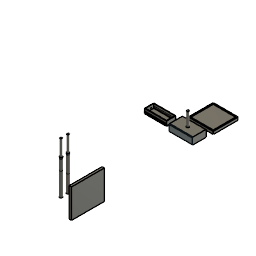
Fuji Personal (Autodesk Fusion 360 design; units mm, degrees)
part number: 2026-10-13-20-22-36-203
Autodesk Fusion 360 part; units mm, degrees
sketch "Sketch1" plane through (0, 0, 0) normal (0, 1, 0) x (1, 0, 0)
  line L0 (-50, 50) -> (50, 50)
  line L1 (50, 50) -> (50, -50)
  line L2 (50, -50) -> (-50, -50)
  line L3 (-50, -50) -> (-50, 50)
  constraint horizontal L0
  constraint vertical L1
  constraint horizontal L2
  constraint vertical L3
sketch "Sketch2" plane through (0, 0, 0) normal (0, 1, 0) x (1, 0, 0)
  line L0 (-95, -40.1567) -> (-192.2, -40.1567)
  line L1 (-192.2, -40.1567) -> (-192.2, 57.0433)
  line L2 (-192.2, 57.0433) -> (-95, 57.0433)
  line L3 (-95, 57.0433) -> (-95, -40.1567)
  dimension "d5" = 97.2
  dimension "d6" = 97.2
  constraint horizontal L0
  constraint vertical L1
  constraint horizontal L2
  constraint vertical L3
  measures "d5" distance of L0.start L2.end
  measures "d6" distance of L0.start L0.end
sketch "Sketch3" plane through (0, 0, 0) normal (0, 1, 0) x (1, 0, 0)
  line L0 (100, -40) -> (-7.2, -40)
  line L1 (-7.2, -40) -> (-7.2, 67.2)
  line L2 (-7.2, 67.2) -> (100, 67.2)
  line L3 (100, 67.2) -> (100, -40)
  dimension "d9" = 107.2
  dimension "d10" = 107.2
  constraint horizontal L0
  constraint vertical L1
  constraint horizontal L2
  constraint vertical L3
  measures "d9" distance of L0.start L0.end
  measures "d10" distance of L0.start L2.end
sketch "Sketch4" plane through (-2.2, 0, 0) normal (-1, 0, 0) x (0, 0, 1)
  line L0 (-62.0433, 10) -> (35.1567, 10)
  line L1 (35.1567, 10) -> (35.1567, 107.2)
  line L2 (35.1567, 107.2) -> (-62.0433, 107.2)
  line L3 (-62.0433, 107.2) -> (-62.0433, 10)
  line L4 (-60, 105) -> (32, 105)
  line L5 (32, 105) -> (32, 13)
  line L6 (32, 13) -> (-60, 13)
  line L7 (-60, 13) -> (-60, 105)
  dimension "d13" = 92
  dimension "d14" = 92
  constraint horizontal L4
  constraint vertical L5
  constraint horizontal L6
  constraint vertical L7
  measures "d13" distance of L4.start L4.end
  measures "d14" distance of L4.start L6.end
sketch "Sketch5" plane through (0, 10, 0) normal (0, 1, 0) x (-1, 0, 0)
  line L0 (-100, -67.2) -> (7.2, -67.2)
  line L1 (7.2, -67.2) -> (7.2, 40)
  line L2 (7.2, 40) -> (-100, 40)
  line L3 (-100, 40) -> (-100, -67.2)
  line L4 (3, -63) -> (6, -63)
  line L5 (6, -63) -> (6, 36)
  line L6 (6, 36) -> (3, 36)
  line L7 (3, 36) -> (3, -63)
  constraint horizontal L4
  constraint vertical L5
  constraint horizontal L6
  constraint vertical L7
sketch "Sketch7" plane through (0, 0, 0) normal (0, -1, 0) x (1, 0, 0)
  line L0 (-7.2, -67.2) -> (100, -67.2)
  line L1 (100, -67.2) -> (100, 40)
  line L2 (100, 40) -> (-7.2, 40)
  line L3 (-7.2, 40) -> (-7.2, -67.2)
  circle A0 centre (46.3894, -13.587) radius 5
  dimension "d20" = 10
  measures "d20" diameter of A0
sketch "Sketch8" plane through (0, 0, 0) normal (0, 1, 0) x (1, 0, 0)
  circle A0 centre (-120, 50) radius 5
  dimension "d23" = 10
  measures "d23" diameter of A0
extrude "Extrude7" add sketch "Sketch8" along normal blind 35 makes body 1
extrude "Extrude8" add 1 faces at (-118.5319, 35, -51.1707) along direction (0, 1, 0) blind 10 on bodies 1 bodies 1
sketch "Sketch9" plane through (0, 0, 0) normal (0, 1, 0) x (1, 0, 0)
  line L0 (-35, -25) -> (-125, -25)
  line L1 (-125, -25) -> (-125, -80)
  line L2 (-125, -80) -> (-35, -80)
  line L3 (-35, -80) -> (-35, -25)
  constraint horizontal L0
  constraint vertical L1
  constraint horizontal L2
  constraint vertical L3
sketch "Sketch10" plane through (0, 4, 0) normal (0, 1, 0) x (-1, 0, 0)
  arc A0 (37.5, 80) -> (35, 77.5) centre (37.5, 77.5) ccw
  line L0 (35, 77.5) -> (35, 27.5)
  arc A1 (35, 27.5) -> (37.5, 25) centre (37.5, 27.5) ccw
  line L1 (37.5, 25) -> (122.5, 25)
  arc A2 (122.5, 25) -> (125, 27.5) centre (122.5, 27.5) ccw
  line L2 (125, 27.5) -> (125, 77.5)
  arc A3 (125, 77.5) -> (122.5, 80) centre (122.5, 77.5) ccw
  line L3 (122.5, 80) -> (37.5, 80)
  line L4 (35, 52.5) -> (125, 52.5)
  line L5 (80, 80) -> (80, 25)
  circle A4 centre (80, 52.5) radius 4.9
  dimension "d34" = 9.8
  constraint midpoint L0 L4.start
  constraint midpoint L2 L4.end
  constraint midpoint L3 L5.start
  constraint midpoint L1 L5.end
  constraint midpoint L5 A4.centre
  measures "d34" diameter of A4
move_body "Move3" bodies 1 to x (1, 0, 0) y (0, 1, 0) z (0, 0, 1) at (40, 0, 102.5)
sketch "Sketch11" plane through (0, 0, 0) normal (0, 1, 0) x (1, 0, 0)
  line L0 (-125, -130) -> (-10, -130)
  line L1 (-10, -130) -> (-10, -150)
  line L2 (-10, -150) -> (-125, -150)
  line L3 (-125, -150) -> (-125, -130)
  line L4 (-125, -150) -> (-10, -150)
  line L5 (-10, -150) -> (-10, -175)
  line L6 (-10, -175) -> (-125, -175)
  line L7 (-125, -175) -> (-125, -150)
  constraint horizontal L0
  constraint vertical L1
  constraint horizontal L2
  constraint vertical L3
  constraint horizontal L4
  constraint vertical L5
  constraint horizontal L6
  constraint vertical L7
sketch "Sketch13" plane through (0, 35, 0) normal (0, 1, 0) x (-1, 0, 0)
  line L0 (125, 175) -> (10, 175)
  line L1 (10, 175) -> (10, 130)
  line L2 (10, 130) -> (125, 130)
  line L3 (125, 130) -> (125, 175)
  line L4 (125, 130) -> (10, 130)
  line L5 (10, 130) -> (10, 175)
  line L6 (10, 175) -> (125, 175)
  line L7 (125, 175) -> (125, 130)
  line L8 (123.5, 131.5) -> (11.5, 131.5)
  line L9 (11.5, 131.5) -> (11.5, 135.5)
  line L10 (11.5, 135.5) -> (123.5, 135.5)
  line L11 (123.5, 135.5) -> (123.5, 131.5)
  line L12 (11.5, 135.5) -> (123, 135.5)
  line L13 (123, 135.5) -> (123, 173.5)
  line L14 (123, 173.5) -> (11.5, 173.5)
  line L15 (11.5, 173.5) -> (11.5, 135.5)
  line L16 (123, 173.5) -> (123.5, 173.5)
  line L17 (123.5, 173.5) -> (123.5, 135.5)
  line L18 (123.5, 135.5) -> (123, 135.5)
  line L19 (123, 135.5) -> (123, 173.5)
  dimension "d41" = 115
  dimension "d42" = 45
  constraint horizontal L4
  constraint vertical L5
  constraint horizontal L6
  constraint vertical L7
  constraint coincident L0.end L1.start
  constraint coincident L2.end L3.start
  constraint horizontal L8
  constraint vertical L9
  constraint horizontal L10
  constraint vertical L11
  constraint horizontal L12
  constraint vertical L13
  constraint horizontal L14
  constraint vertical L15
  constraint horizontal L16
  constraint vertical L17
  constraint horizontal L18
  constraint vertical L19
  measures "d41" distance of L2.end L1.end
  measures "d42" distance of L2.end L0.start
sketch "Sketch14" plane through (0, 54.4449, 0) normal (0, 1, 0) x (-1, 0, 0)
  arc A0 (133.3754, 102.0813) -> (129.3754, 106.0813) centre (129.3754, 102.0813) ccw
  line L0 (129.3754, 106.0813) -> (30.1754, 106.0813)
  arc A1 (30.1754, 106.0813) -> (26.1754, 102.0813) centre (30.1754, 102.0813) ccw
  line L1 (26.1754, 102.0813) -> (26.1754, 2.8813)
  arc A2 (26.1754, 2.8813) -> (30.1754, -1.1187) centre (30.1754, 2.8813) ccw
  line L2 (30.1754, -1.1187) -> (129.3754, -1.1187)
  arc A3 (129.3754, -1.1187) -> (133.3754, 2.8813) centre (129.3754, 2.8813) ccw
  line L3 (133.3754, 2.8813) -> (133.3754, 102.0813)
  line L4 (129.1754, 102.0813) -> (132.1754, 102.0813)
  line L5 (132.1754, 102.0813) -> (132.1754, 3.0813)
  line L6 (132.1754, 3.0813) -> (129.1754, 3.0813)
  line L7 (129.1754, 3.0813) -> (129.1754, 102.0813)
  line L8 (-78, 108) -> (-175, 108)
  line L9 (-175, 108) -> (-175, 205)
  line L10 (-175, 205) -> (-78, 205)
  line L11 (-78, 205) -> (-78, 108)
  line L12 (-50, -50) -> (-147.2, -50)
  line L13 (-147.2, -50) -> (-147.2, 47.2)
  line L14 (-147.2, 47.2) -> (-50, 47.2)
  line L15 (-50, 47.2) -> (-50, -50)
  dimension "d47" = 97.2
  dimension "d48" = 97.2
  constraint horizontal L8
  constraint vertical L9
  constraint horizontal L10
  constraint vertical L11
  constraint horizontal L12
  constraint vertical L13
  constraint horizontal L14
  constraint vertical L15
  measures "d47" distance of L12.start L12.end
  measures "d48" distance of L12.start L14.end
sketch "Sketch15" plane through (0, 0, 0) normal (0, 1, 0) x (1, 0, 0)
  line L0 (-25, -200) -> (-35, -200)
  line L1 (-35, -200) -> (-35, -525)
  line L2 (-35, -525) -> (-25, -525)
  line L3 (-25, -525) -> (-25, -200)
  dimension "d53" = 10
  constraint horizontal L0
  constraint vertical L1
  constraint horizontal L2
  constraint vertical L3
  measures "d53" distance of L0.start L0.end
sketch "Sketch16" plane through (0, 0, 0) normal (0, 1, 0) x (1, 0, 0)
  line L0 (-25, -250) -> (-70, -250)
  line L1 (-70, -250) -> (-70, -475)
  line L2 (-70, -475) -> (-25, -475)
  line L3 (-25, -475) -> (-25, -250)
  constraint horizontal L0
  constraint vertical L1
  constraint horizontal L2
  constraint vertical L3
sketch "Sketch17" plane through (0, 20, 0) normal (0, 1, 0) x (-1, 0, 0)
  line L0 (25, 475) -> (25, 250)
  line L1 (25, 250) -> (70, 250)
  line L2 (70, 250) -> (70, 475)
  line L3 (70, 475) -> (25, 475)
  line L4 (25, 250) -> (70, 250)
  line L5 (70, 250) -> (70, 475)
  line L6 (70, 475) -> (25, 475)
  line L7 (25, 475) -> (25, 250)
  line L8 (25, 362.5) -> (70, 362.5)
  line L9 (25, 425) -> (70, 425)
  line L10 (25, 300) -> (70, 300)
  circle A0 centre (35, 420) radius 5
  circle A1 centre (35, 305) radius 5
  constraint horizontal L4
  constraint vertical L5
  constraint horizontal L6
  constraint vertical L7
  constraint coincident L2.end L3.start
  constraint coincident L0.end L1.start
  constraint midpoint L7 L8.start
  constraint midpoint L5 L8.end
  constraint coincident L7 L9.start
  constraint coincident L2 L9.end
  constraint perpendicular L2 L9
  constraint coincident L7 L10.start
  constraint coincident L5 L10.end
  constraint perpendicular L5 L10
  constraint tangent L9 A0
sketch "Sketch18" plane through (0, 20, 0) normal (0, 1, 0) x (-1, 0, 0)
  circle A0 centre (35, 420) radius 5
  circle A1 centre (35, 305) radius 5
  line L0 (25, 475) -> (25, 250)
  line L1 (25, 250) -> (70, 250)
  line L2 (70, 250) -> (70, 475)
  line L3 (70, 475) -> (25, 475)
  circle A2 centre (-25, 325) radius 5
  circle A3 centre (-25, 370) radius 5
  dimension "d58" = 10
  dimension "d59" = 10
  measures "d58" diameter of A2
  measures "d59" diameter of A3
sketch "Sketch19" plane through (0, 20, 0) normal (0, 1, 0) x (-1, 0, 0)
  circle A0 centre (35, 420) radius 5
  circle A1 centre (35, 305) radius 5
  line L0 (25, 475) -> (25, 250)
  line L1 (25, 250) -> (70, 250)
  line L2 (70, 250) -> (70, 475)
  line L3 (70, 475) -> (25, 475)
  line L4 (60, 255) -> (65, 255)
  line L5 (65, 255) -> (65, 470)
  line L6 (65, 470) -> (60, 470)
  line L7 (60, 470) -> (60, 255)
  constraint horizontal L4
  constraint vertical L5
  constraint horizontal L6
  constraint vertical L7
sketch "Sketch20" plane through (0, 0, 0) normal (0, 1, 0) x (1, 0, 0)
sketch "Sketch21" plane through (-70, 0, 0) normal (-1, 0, 0) x (0, 0, 1)
  line L0 (470, 0) -> (470, 20)
  line L1 (470, 20) -> (255, 20)
  line L2 (255, 20) -> (255, 0)
  line L3 (255, 0) -> (470, 0)
  line L4 (255, 20) -> (470, 20)
  line L5 (470, 20) -> (470, 0)
  line L6 (470, 0) -> (255, 0)
  line L7 (255, 0) -> (255, 20)
  line L8 (362.5, 20) -> (362.5, 0)
  line L9 (312.4786, 5.2501) -> (412.5265, 5.3043) construction
  line L10 (412.5265, 5.3043) -> (412.5214, 14.7499) construction
  line L11 (412.5214, 14.7499) -> (312.4735, 14.6957) construction
  line L12 (312.4735, 14.6957) -> (312.4786, 5.2501) construction
  dimension "d68" = 10
  constraint horizontal L4
  constraint vertical L5
  constraint horizontal L6
  constraint vertical L7
  constraint coincident L0.start L3.end
  constraint coincident L1.end L2.start
  constraint midpoint L4 L8.start
  constraint midpoint L3 L8.end
  constraint midpoint L8
move_face "MoveFace1" to x (1, 0, 0) y (0, 1, 0) z (0, 0, 1) at (-101.024, 0, -37.3383) 1 faces at (-75.0248, 15, 52.9978) on bodies 1
extrude "Extrude23" add 1 faces at (-179.5559, 45, 13.9909) along direction (0, 1, 0) blind 5 on bodies 1 bodies 1
sketch "Sketch22" plane through (0, 0, 0) normal (0, 0, 1) x (1, 0, 0)
sketch "Sketch23" plane through (0, 0, 0) normal (0, 1, 0) x (1, 0, 0)
  line L0 (70, 5) -> (80, 5)
  line L1 (80, 5) -> (80, 147)
  line L2 (80, 147) -> (70, 147)
  line L3 (70, 147) -> (70, 5)
  dimension "d84" = 142
  constraint horizontal L0
  constraint vertical L1
  constraint horizontal L2
  constraint vertical L3
  measures "d84" distance of L0.start L2.end
extrude "Extrude24" add sketch "Sketch23" along normal blind 125 separate body makes body 2
move_body "Move13" bodies 2 to x (1, 0, 0) y (0, 1, 0) z (0, 0, 1) at (0, 0, 460)
move_body "Move14" bodies 2 to x (1, 0, 0) y (0, 1, 0) z (0, 0, 1) at (-65, 20, 190)
sketch "Sketch24" plane through (0, 0, 0) normal (0, 1, 0) x (1, 0, 0)
  circle A0 centre (30, -675) radius 5
  dimension "d87" = 10
  measures "d87" diameter of A0
extrude "Extrude26" add 1 faces at (-179.5559, 50, 13.9909) along direction (0, 1, 0) blind 10 on bodies 1 bodies 1
sketch "Sketch25" plane through (0, 0, 0) normal (0, 1, 0) x (1, 0, 0)
  line L0 (-25, -25) -> (-125, -25)
  line L1 (-125, -25) -> (-125, -85)
  line L2 (-125, -85) -> (-25, -85)
  line L3 (-25, -85) -> (-25, -25)
  dimension "d94" = 60
  dimension "d95" = 100
  constraint horizontal L0
  constraint vertical L1
  constraint horizontal L2
  constraint vertical L3
  measures "d94" distance of L0.start L2.end
  measures "d95" distance of L1.end L2.end
extrude "Extrude27" add sketch "Sketch25" along normal blind 30 separate body makes body 3
sketch "Sketch27" plane through (-125, 0, 0) normal (-1, 0, 0) x (0, 0, 1)
  line L0 (35, 25) -> (75, 25)
  line L1 (75, 25) -> (75, 5)
  line L2 (75, 5) -> (35, 5)
  line L3 (35, 5) -> (35, 25)
  constraint horizontal L0
  constraint vertical L1
  constraint horizontal L2
  constraint vertical L3
sketch "Sketch28" plane through (-125, 0, 0) normal (-1, 0, 0) x (0, 0, 1)
sketch "Sketch29" plane through (0, 0, 0) normal (0, 1, 0) x (1, 0, 0)
  line L0 (-150, -50) -> (-170, -50)
  line L1 (-170, -50) -> (-170, -90)
  line L2 (-170, -90) -> (-150, -90)
  line L3 (-150, -90) -> (-150, -50)
  constraint horizontal L0
  constraint vertical L1
  constraint horizontal L2
  constraint vertical L3
extrude "Extrude28" cut sketch "Sketch27" against normal blind 95 bodies 3
extrude "Extrude29" add sketch "Sketch29" along normal blind 95 separate body makes body 4
move_body "Move17" bodies 4 to x (0, -1, 0) y (1, 0, 0) z (0, 0, 1) at (-389.9052, -145.0948, 0)
sketch "Sketch30" plane through (0, 0, 85) normal (0, 0, 1) x (1, 0, 0)
  line L0 (-125, 0) -> (-25, 0)
  line L1 (-25, 0) -> (-25, 30)
  line L2 (-25, 30) -> (-125, 30)
  line L3 (-125, 30) -> (-125, 0)
sketch "Sketch31" plane through (0, 0, 50) normal (0, 0, -1) x (-1, 0, 0)
  line L0 (389.9052, 4.9052) -> (389.9052, 24.9052)
  line L1 (389.9052, 24.9052) -> (294.9052, 24.9052)
  line L2 (294.9052, 24.9052) -> (294.9052, 4.9052)
  line L3 (294.9052, 4.9052) -> (389.9052, 4.9052)
  line L4 (300, 15) -> (375, 15)
  line L5 (375, 15) -> (375, 10)
  line L6 (375, 10) -> (300, 10)
  line L7 (300, 10) -> (300, 15)
  dimension "d102" = 75
  dimension "d103" = 5
  constraint horizontal L4
  constraint vertical L5
  constraint horizontal L6
  constraint vertical L7
  measures "d102" distance of L4.start L4.end
  measures "d103" distance of L4.start L6.end
sketch "Sketch32" plane through (0, 0, 90) normal (0, 0, 1) x (1, 0, 0)
  line L0 (-389.9052, 24.9052) -> (-389.9052, 4.9052)
  line L1 (-389.9052, 4.9052) -> (-294.9052, 4.9052)
  line L2 (-294.9052, 4.9052) -> (-294.9052, 24.9052)
  line L3 (-294.9052, 24.9052) -> (-389.9052, 24.9052)
  line L4 (-380, 15) -> (-305, 15)
  line L5 (-305, 15) -> (-305, 10)
  line L6 (-305, 10) -> (-380, 10)
  line L7 (-380, 10) -> (-380, 15)
  constraint horizontal L4
  constraint vertical L5
  constraint horizontal L6
  constraint vertical L7
extrude "Extrude30" add sketch "Sketch32" along normal blind 1 contours L4 L5 L6 L7 bodies 4
extrude "Extrude31" add sketch "Sketch31" along normal blind 1 contours L4 L5 L6 L7 bodies 4
sketch "Sketch33" plane through (0, 24.9052, 0) normal (0, 1, 0) x (-1, 0, 0)
  line L0 (389.9052, 50) -> (389.9052, 90)
  line L1 (389.9052, 90) -> (294.9052, 90)
  line L2 (294.9052, 90) -> (294.9052, 50)
  line L3 (294.9052, 50) -> (389.9052, 50)
  line L4 (297, 88) -> (387, 88)
  line L5 (387, 88) -> (387, 52)
  line L6 (387, 52) -> (297, 52)
  line L7 (297, 52) -> (297, 88)
  line L8 (387, 88) -> (388, 88)
  line L9 (388, 88) -> (388, 52)
  line L10 (388, 52) -> (387, 52)
  line L11 (387, 52) -> (387, 88)
  constraint horizontal L4
  constraint vertical L5
  constraint horizontal L6
  constraint vertical L7
  constraint horizontal L8
  constraint vertical L9
  constraint horizontal L10
  constraint vertical L11
extrude "Extrude32" cut sketch "Sketch33" against normal blind 17.5 contours L4 L5 L6 L7 L11 | L5 L8 L9 L10 L11 bodies 4
sketch "Sketch35" plane through (0, 0, 35) normal (0, 0, 1) x (1, 0, 0)
  line L0 (-125, 25) -> (-125, 5)
  line L1 (-125, 5) -> (-30, 5)
  line L2 (-30, 5) -> (-30, 25)
  line L3 (-30, 25) -> (-125, 25)
  line L4 (-125, 15) -> (-55, 15)
  line L5 (-55, 15) -> (-55, 10)
  line L6 (-55, 10) -> (-125, 10)
  line L7 (-125, 10) -> (-125, 15)
  constraint horizontal L4
  constraint vertical L5
  constraint horizontal L6
  constraint vertical L7
  constraint midpoint L0 L4.start
extrude "Extrude33" cut sketch "Sketch35" against normal blind 1 contours L0 L4 L5 L6 L7 bodies 3
sketch "Sketch36" plane through (0, 0, 75) normal (0, 0, -1) x (-1, 0, 0)
  line L0 (125, 5) -> (125, 25)
  line L1 (125, 25) -> (30, 25)
  line L2 (30, 25) -> (30, 5)
  line L3 (30, 5) -> (125, 5)
  line L4 (125, 15) -> (55, 15)
  line L5 (55, 15) -> (55, 10)
  line L6 (55, 10) -> (125, 10)
  line L7 (125, 10) -> (125, 15)
  constraint horizontal L4
  constraint vertical L5
  constraint horizontal L6
  constraint vertical L7
  constraint midpoint L0 L4.start
extrude "Extrude34" cut sketch "Sketch36" against normal blind 1 contours L0 L4 L5 L6 L7 bodies 3
sketch "Sketch37" plane through (0, 0, 50) normal (0, 0, -1) x (-1, 0, 0)
extrude "Extrude35" cut 1 faces at (-325, 11.6667, 49) along direction (0, 0, 1) blind 1 on bodies 4 bodies 4
sketch "Sketch38" plane through (0, 0, 91) normal (0, 0, 1) x (1, 0, 0)
  line L0 (-380, 10) -> (-305, 10)
  line L1 (-305, 10) -> (-305, 15)
  line L2 (-305, 15) -> (-380, 15)
  line L3 (-380, 15) -> (-380, 10)
  line L4 (-380, 15) -> (-305, 15)
  line L5 (-305, 15) -> (-305, 10)
  line L6 (-305, 10) -> (-380, 10)
  line L7 (-380, 10) -> (-380, 15)
  constraint horizontal L4
  constraint vertical L5
  constraint horizontal L6
  constraint vertical L7
  constraint coincident L0.end L1.start
  constraint coincident L2.end L3.start
extrude "Extrude36" cut sketch "Sketch38" against normal blind 1 bodies 4
sketch "Sketch39" plane through (0, 0, 90) normal (0, 0, 1) x (1, 0, 0)
  line L0 (-389.9052, 24.9052) -> (-389.9052, 4.9052)
  line L1 (-389.9052, 4.9052) -> (-294.9052, 4.9052)
  line L2 (-294.9052, 4.9052) -> (-294.9052, 24.9052)
  line L3 (-294.9052, 24.9052) -> (-389.9052, 24.9052)
  line L4 (-294.91, 15) -> (-364.91, 15)
  line L5 (-364.91, 15) -> (-364.91, 10)
  line L6 (-364.91, 10) -> (-294.91, 10)
  line L7 (-294.91, 10) -> (-294.91, 15)
  dimension "d118" = 70
  dimension "d119" = 5
  constraint horizontal L4
  constraint vertical L5
  constraint horizontal L6
  constraint vertical L7
  measures "d118" distance of L4.start L4.end
  measures "d119" distance of L4.start L6.end
extrude "Extrude37" add sketch "Sketch39" along normal blind 1 contours L4 L5 L6 L7 bodies 4
sketch "Sketch40" plane through (0, 0, 50) normal (0, 0, -1) x (-1, 0, 0)
sketch "Sketch41" plane through (0, 0, 50) normal (0, 0, -1) x (-1, 0, 0)
  line L0 (300, 15) -> (295, 15)
  line L1 (295, 15) -> (295, 10)
  line L2 (295, 10) -> (300, 10)
  line L3 (300, 10) -> (300, 15)
  line L4 (300, 15) -> (365, 15)
  line L5 (365, 15) -> (365, 10)
  line L6 (365, 10) -> (300, 10)
  line L7 (300, 10) -> (300, 15)
  constraint horizontal L0
  constraint vertical L1
  constraint horizontal L2
  constraint vertical L3
  constraint horizontal L4
  constraint vertical L5
  constraint horizontal L6
  constraint vertical L7
extrude "Extrude38" add sketch "Sketch41" along normal blind 1 bodies 4
sketch "Sketch42" plane through (0, 0, 50) normal (0, 0, -1) x (1, 0, 0)
sketch "Sketch43" plane through (-389.9052, 0, 0) normal (-1, 0, 0) x (0, 0, 1)
  line L0 (50, 4.9052) -> (90, 4.9052)
  line L1 (90, 4.9052) -> (90, 24.9052)
  line L2 (90, 24.9052) -> (50, 24.9052)
  line L3 (50, 24.9052) -> (50, 4.9052)
  line L4 (60, 15) -> (80, 15)
  line L5 (80, 15) -> (80, 10)
  line L6 (80, 10) -> (60, 10)
  line L7 (60, 10) -> (60, 15)
  constraint horizontal L4
  constraint vertical L5
  constraint horizontal L6
  constraint vertical L7
extrude "Extrude39" add sketch "Sketch43" along normal blind 10 contours L4 L5 L6 L7 bodies 4
sketch "Sketch44" plane through (0, 15, 0) normal (0, 1, 0) x (-1, 0, 0)
  line L0 (389.9052, 80) -> (389.9052, 60)
  line L1 (389.9052, 60) -> (399.9052, 60)
  line L2 (399.9052, 60) -> (399.9052, 80)
  line L3 (399.9052, 80) -> (389.9052, 80)
  line L4 (389.9052, 74.8716) -> (395, 74.8716)
  line L5 (395, 74.8716) -> (395, 65)
  line L6 (395, 65) -> (389.9052, 65)
  line L7 (389.9052, 65) -> (389.9052, 74.8716)
  constraint horizontal L4
  constraint vertical L5
  constraint horizontal L6
  constraint vertical L7
  constraint coincident L0 L4.start
extrude "Extrude40" cut sketch "Sketch44" against normal blind 40 contours L0 L4 L5 L6 L7 bodies 4
fillet "Fillet10" radius 2 1 edges at (-389.9052, 14.9052, 90) on bodies 4
fillet "Fillet11" radius 2 1 edges at (-389.9052, 14.9052, 50) on bodies 4
fillet "Fillet12" radius 2 2 edges at (-399.9052, 12.5, 60) (-399.9052, 12.5, 80) on bodies 4
sketch "Sketch45" plane through (0, 30, 0) normal (0, 1, 0) x (-1, 0, 0)
  line L0 (25, 85) -> (25, 25)
  line L1 (25, 25) -> (125, 25)
  line L2 (125, 25) -> (125, 85)
  line L3 (125, 85) -> (25, 85)
  line L4 (125, 25) -> (25, 25)
  line L5 (25, 25) -> (25, 85)
  line L6 (25, 85) -> (125, 85)
  line L7 (125, 85) -> (125, 25)
  line L8 (75, 25) -> (75, 85)
  line L9 (125, 55) -> (25, 55)
  circle A0 centre (75, 55) radius 5
  dimension "d134" = 10
  constraint horizontal L4
  constraint vertical L5
  constraint horizontal L6
  constraint vertical L7
  constraint coincident L0.start L3.end
  constraint coincident L1.end L2.start
  constraint midpoint L4 L8.start
  constraint midpoint L6 L8.end
  constraint midpoint L2 L9.start
  constraint midpoint L5 L9.end
  constraint midpoint L8 A0.centre
  measures "d134" diameter of A0
extrude "Extrude41" cut sketch "Sketch45" against normal blind 4 contours L8 L9 A0 | L8 L9 A0 | L8 L9 A0 | L8 L9 A0 bodies 3
fillet "Fillet13" radius 2 1 edges at (-75, 30, 25) on bodies 3
fillet "Fillet14" radius 2 1 edges at (-75, 30, 85) on bodies 3
move_body "Move18" bodies 1 to x (1, 0, 0) y (0, 1, 0) z (0, 0, 1) at (106.0604, 28.7463, 39.3613)
fillet "Fillet15" radius 2 2 edges at (-75, 0, 25) (-75, 0, 85) on bodies 3
move_body "Move19" bodies 4 to x (1, 0, 0) y (0, 1, 0) z (0, 0, 1) at (135, 0, -15)
move_body "Move20" bodies 4 to x (1, 0, 0) y (0, 1, 0) z (0, 0, 1) at (65, 0, 0)
delete_face "DeleteFace1" 1 faces at (-188.2837, 11.5718, 35.0361) on bodies 4
delete_face "DeleteFace2" 1 faces at (-188.3767, 18.2385, 74.9436) on bodies 4
move_body "Move21" bodies 4 to x (1, 0, 0) y (0, 1, 0) z (0, 0, 1) at (-6, 0, 0)
sketch "Sketch46" plane through (0, 0, 35) normal (0, 0, -1) x (-1, 0, 0)
  line L0 (171, 15) -> (171, 10)
  line L1 (171, 10) -> (101, 10)
  line L2 (101, 10) -> (101, 15)
  line L3 (101, 15) -> (171, 15)
  line L4 (195.9052, 4.9052) -> (195.9052, 24.9052)
  line L5 (195.9052, 24.9052) -> (100.9052, 24.9052)
  line L6 (100.9052, 24.9052) -> (100.9052, 4.9052)
  line L7 (100.9052, 4.9052) -> (195.9052, 4.9052)
  line L8 (171, 15) -> (195.9052, 15)
  line L9 (195.9052, 15) -> (195.9052, 10.0075)
  line L10 (195.9052, 10.0075) -> (171, 10.0075)
  line L11 (171, 10.0075) -> (171, 15)
  constraint horizontal L8
  constraint vertical L9
  constraint horizontal L10
  constraint vertical L11
  constraint coincident L4 L9.end
  constraint coincident L0.start L3.end
extrude "Extrude42" add sketch "Sketch46" along normal blind 1 contours L0 L4 L8 L9 L10 L11 bodies 4
sketch "Sketch47" plane through (0, 0, 75) normal (0, 0, 1) x (1, 0, 0)
  line L0 (-100.91, 10) -> (-170.91, 10)
  line L1 (-170.91, 10) -> (-170.91, 15)
  line L2 (-170.91, 15) -> (-100.91, 15)
  line L3 (-100.91, 15) -> (-100.91, 10)
  line L4 (-195.9052, 24.9052) -> (-195.9052, 4.9052)
  line L5 (-195.9052, 4.9052) -> (-100.9052, 4.9052)
  line L6 (-100.9052, 4.9052) -> (-100.9052, 24.9052)
  line L7 (-100.9052, 24.9052) -> (-195.9052, 24.9052)
  line L8 (-170.91, 15) -> (-195.9052, 15)
  line L9 (-195.9052, 15) -> (-195.9052, 9.9804)
  line L10 (-195.9052, 9.9804) -> (-170.91, 9.9804)
  line L11 (-170.91, 9.9804) -> (-170.91, 15)
  constraint horizontal L8
  constraint vertical L9
  constraint horizontal L10
  constraint vertical L11
  constraint coincident L4 L9.end
  constraint coincident L1.end L2.start
extrude "Extrude43" add sketch "Sketch47" along normal blind 1 contours L1 L4 L8 L9 L10 L11 bodies 4
sketch "Sketch48" plane through (0, 0, 35) normal (0, 0, -1) x (1, 0, 0)
  line L0 (-172, -15) -> (-170, -15)
  line L1 (-170, -15) -> (-170, -10)
  line L2 (-170, -10) -> (-172, -10)
  line L3 (-172, -10) -> (-172, -15)
  constraint horizontal L0
  constraint vertical L1
  constraint horizontal L2
  constraint vertical L3
extrude "Extrude44" add sketch "Sketch48" along normal blind 1.5 bodies 4
sketch "Sketch49" plane through (0, 0, 75) normal (0, 0, 1) x (1, 0, 0)
  line L0 (-172, 15) -> (-170, 15)
  line L1 (-170, 15) -> (-170, 10)
  line L2 (-170, 10) -> (-172, 10)
  line L3 (-172, 10) -> (-172, 15)
  constraint horizontal L0
  constraint vertical L1
  constraint horizontal L2
  constraint vertical L3
extrude "Extrude45" add sketch "Sketch49" along normal blind 1.5 bodies 4
move_body "Move22" bodies 4 to x (1, 0, 0) y (0, 1, 0) z (0, 0, 1) at (-45, 0, 0)
sketch "Sketch50" plane through (0, 0, 34) normal (0, 0, 1) x (1, 0, 0)
  line L0 (-125, 10) -> (-55, 10)
  line L1 (-55, 10) -> (-55, 15)
  line L2 (-55, 15) -> (-125, 15)
  line L3 (-125, 15) -> (-125, 10)
  line L4 (-125, 15) -> (-101.095, 15)
  line L5 (-101.095, 15) -> (-101.095, 10)
  line L6 (-101.095, 10) -> (-125, 10)
  line L7 (-125, 10) -> (-125, 15)
  line L8 (-101.095, 15) -> (-99.095, 15)
  line L9 (-99.095, 15) -> (-99.095, 10)
  line L10 (-99.095, 10) -> (-101.095, 10)
  line L11 (-101.095, 10) -> (-101.095, 15)
  dimension "d151" = 23.905
  dimension "d152" = 2
  constraint horizontal L4
  constraint vertical L5
  constraint horizontal L6
  constraint vertical L7
  constraint coincident L0 L5.end
  constraint coincident L2.end L3.start
  constraint horizontal L8
  constraint vertical L9
  constraint horizontal L10
  constraint vertical L11
  measures "d151" distance of L2.end L4.end
  measures "d152" distance of L4.end L8.end
extrude "Extrude46" cut sketch "Sketch50" against normal blind 0.5 contours L0 L2 L5 L8 L9 L10 L11 bodies 3
sketch "Sketch51" plane through (0, 0, 76) normal (0, 0, -1) x (-1, 0, 0)
  line L0 (125, 10) -> (125, 15)
  line L1 (125, 15) -> (55, 15)
  line L2 (55, 15) -> (55, 10)
  line L3 (55, 10) -> (125, 10)
  line L4 (125, 15) -> (101.095, 15)
  line L5 (101.095, 15) -> (101.095, 10)
  line L6 (101.095, 10) -> (125, 10)
  line L7 (125, 10) -> (125, 15)
  line L8 (101.095, 15) -> (99.095, 15)
  line L9 (99.095, 15) -> (99.095, 10)
  line L10 (99.095, 10) -> (101.095, 10)
  line L11 (101.095, 10) -> (101.095, 15)
  dimension "d155" = 23.905
  dimension "d156" = 5
  dimension "d157" = 2
  constraint horizontal L4
  constraint vertical L5
  constraint horizontal L6
  constraint vertical L7
  constraint coincident L0.end L1.start
  constraint horizontal L8
  constraint vertical L9
  constraint horizontal L10
  constraint vertical L11
  constraint coincident L3 L9.end
  measures "d155" distance of L0.end L4.end
  measures "d156" distance of L0.end L0.start
  measures "d157" distance of L4.end L8.end
extrude "Extrude47" cut sketch "Sketch51" against normal blind 0.5 contours L1 L3 L5 L8 L9 L10 L11 bodies 3
fillet "Fillet16" radius 0.25 2 edges at (-215, 12.5, 33.5) (-217, 12.5, 33.5) on bodies 4
fillet "Fillet17" radius 0.25 2 edges at (-217, 12.5, 76.5) (-215, 12.5, 76.5) on bodies 4
sketch "Sketch52" plane through (0, 0, 0) normal (0, 1, 0) x (1, 0, 0)
  line L0 (-175, 5) -> (-272.5, 5)
  line L1 (-272.5, 5) -> (-272.5, 102.5)
  line L2 (-272.5, 102.5) -> (-175, 102.5)
  line L3 (-175, 102.5) -> (-175, 5)
  line L4 (-170, 0) -> (-277.5, 0)
  line L5 (-277.5, 0) -> (-277.5, 107.5)
  line L6 (-277.5, 107.5) -> (-170, 107.5)
  line L7 (-170, 107.5) -> (-170, 0)
  dimension "d164" = 97.5
  dimension "d165" = 97.5
  dimension "d166" = 107.5
  dimension "d167" = 107.5
  constraint horizontal L0
  constraint vertical L1
  constraint horizontal L2
  constraint vertical L3
  constraint horizontal L4
  constraint vertical L5
  constraint horizontal L6
  constraint vertical L7
  measures "d164" distance of L0.start L2.end
  measures "d165" distance of L0.start L0.end
  measures "d166" distance of L4.start L6.end
  measures "d167" distance of L4.start L4.end
extrude "Extrude48" add sketch "Sketch52" along normal blind 12 separate body makes body 5
sketch "Sketch53" plane through (0, 0, 0) normal (0, 1, 0) x (1, 0, 0)
  line L0 (-175, 5) -> (-272.5, 5)
  line L1 (-272.5, 5) -> (-272.5, 102.5)
  line L2 (-272.5, 102.5) -> (-175, 102.5)
  line L3 (-175, 102.5) -> (-175, 5)
  dimension "d170" = 97.5
  dimension "d171" = 97.5
  constraint horizontal L0
  constraint vertical L1
  constraint horizontal L2
  constraint vertical L3
  measures "d170" distance of L0.start L2.end
  measures "d171" distance of L0.start L0.end
extrude "Extrude49" add sketch "Sketch53" along normal blind 10.5 bodies 5
fillet "Fillet18" radius 1 4 edges at (-175, 11.25, -5) (-175, 11.25, -102.5) (-272.5, 11.25, -102.5) (-272.5, 11.25, -5) on bodies 5
sketch "Sketch54" plane through (0, 12, 0) normal (0, 1, 0) x (-1, 0, 0)
  line L0 (271.5, -102.5) -> (176, -102.5)
  arc A0 (175, -101.5) -> (176, -102.5) centre (176, -101.5) ccw
  line L1 (175, -101.5) -> (175, -6)
  arc A1 (176, -5) -> (175, -6) centre (176, -6) ccw
  line L2 (176, -5) -> (271.5, -5)
  arc A2 (272.5, -6) -> (271.5, -5) centre (271.5, -6) ccw
  line L3 (272.5, -6) -> (272.5, -101.5)
  arc A3 (271.5, -102.5) -> (272.5, -101.5) centre (271.5, -101.5) ccw
  line L4 (170, -107.5) -> (277.5, -107.5)
  line L5 (277.5, -107.5) -> (277.5, 0)
  line L6 (277.5, 0) -> (170, 0)
  line L7 (170, 0) -> (170, -107.5)
  line L8 (274, -3) -> (276, -3)
  line L9 (276, -3) -> (276, -103)
  line L10 (276, -103) -> (274, -103)
  line L11 (274, -103) -> (274, -3)
  line L12 (274, -103) -> (276, -103)
  line L13 (276, -103) -> (276, -105)
  line L14 (276, -105) -> (274, -105)
  line L15 (274, -105) -> (274, -103)
  constraint horizontal L8
  constraint vertical L9
  constraint horizontal L10
  constraint vertical L11
  constraint horizontal L12
  constraint vertical L13
  constraint horizontal L14
  constraint vertical L15
extrude "Extrude50" add sketch "Sketch54" along normal blind 1.5 contours L8 L9 L10 L11 L12 | L10 L12 L13 L14 L15 bodies 5
fillet "Fillet19" radius 0.5 2 edges at (-276, 12.75, -105) (-274, 12.75, -105) on bodies 5
fillet "Fillet20" radius 0.5 2 edges at (-276, 12.75, -3) (-274, 12.75, -3) on bodies 5
fillet "Fillet21" radius 1 4 edges at (-277.5, 6, 0) (-170, 6, 0) (-277.5, 6, -107.5) (-170, 6, -107.5) on bodies 5
sketch "Sketch55" plane through (0, 0, 0) normal (0, -1, 0) x (1, 0, 0)
  arc A0 (-171, -107.5) -> (-170, -106.5) centre (-171, -106.5) ccw
  line L0 (-170, -106.5) -> (-170, -1)
  arc A1 (-170, -1) -> (-171, 0) centre (-171, -1) ccw
  line L1 (-171, 0) -> (-276.5, 0)
  arc A2 (-276.5, 0) -> (-277.5, -1) centre (-276.5, -1) ccw
  line L2 (-277.5, -1) -> (-277.5, -106.5)
  arc A3 (-277.5, -106.5) -> (-276.5, -107.5) centre (-276.5, -106.5) ccw
  line L3 (-276.5, -107.5) -> (-171, -107.5)
  line L4 (-223.75, -107.5) -> (-223.75, 0)
  line L5 (-277.5, -53.75) -> (-170, -53.75)
  circle A4 centre (-223.75, -53.75) radius 5
  dimension "d184" = 10
  constraint midpoint L3 L4.start
  constraint midpoint L1 L4.end
  constraint midpoint L2 L5.start
  constraint midpoint L0 L5.end
  constraint midpoint L4 A4.centre
  measures "d184" diameter of A4
extrude "Extrude51" cut sketch "Sketch55" against normal blind 3 contours L4 L5 A4 | L4 L5 A4 | L4 L5 A4 | L4 L5 A4 bodies 5
sketch "Sketch56" plane through (0, 0, 0) normal (0, 1, 0) x (1, 0, 0)
  circle A0 centre (-150, -530) radius 5
  circle A1 centre (-115, -530) radius 6.25
  dimension "d187" = 10
  dimension "d188" = 12.5
  measures "d187" diameter of A0
  measures "d188" diameter of A1
extrude "Extrude52" add sketch "Sketch56" along normal blind 150 separate body contours A1 makes body 6
sketch "Sketch57" plane through (0, 150, 0) normal (0, 1, 0) x (-1, 0, 0)
  circle A0 centre (115, 530) radius 6.25
  circle A1 centre (115, 530) radius 4.75
  dimension "d191" = 9.5
  constraint concentric A0 A1
  measures "d191" diameter of A1
extrude "Extrude53" cut sketch "Sketch57" against normal blind 75 contours A1 bodies 6
sketch "Sketch58" plane through (0, 0, 0) normal (0, 1, 0) x (1, 0, 0)
  circle A0 centre (-75, -535) radius 4.75
  dimension "d194" = 9.5
  measures "d194" diameter of A0
extrude "Extrude54" add sketch "Sketch58" along normal blind 75 separate body makes body 7
move_body "Move24" bodies 7 to x (1, 0, 0) y (0, 1, 0) z (0, 0, 1) at (-40, 145, -5)
sketch "Sketch59" plane through (0, 0, 0) normal (1, 0, 0) x (0, 0, -1)
sketch "Sketch60" plane through (0, 145, 0) normal (0, -1, 0) x (1, 0, 0)
  circle A0 centre (-115, 530) radius 4.75
sketch "Sketch61" plane through (0, 0, 0) normal (0, 1, 0) x (1, 0, 0)
sketch "Sketch62" plane through (0, 0, 0) normal (0, 1, 0) x (1, 0, 0)
  circle A0 centre (-115, -560) radius 6.25
  dimension "d197" = 12.5
  measures "d197" diameter of A0
extrude "Extrude55" add sketch "Sketch62" along normal blind 175 separate body makes body 8
sketch "Sketch63" plane through (0, 175, 0) normal (0, 1, 0) x (-1, 0, 0)
  circle A0 centre (115, 560) radius 6.25
  circle A1 centre (115, 560) radius 4.75
  dimension "d200" = 9.5
  constraint concentric A0 A1
  measures "d200" diameter of A1
extrude "Extrude56" cut sketch "Sketch63" against normal blind 75 contours A1 bodies 8
sketch "Sketch64" plane through (0, 0, 0) normal (0, 1, 0) x (1, 0, 0)
  circle A0 centre (-75, -560) radius 4.75
  dimension "d203" = 9.5
  measures "d203" diameter of A0
extrude "Extrude57" add sketch "Sketch64" along normal blind 75 separate body makes body 9
move_body "Move25" bodies 9 to x (1, 0, 0) y (0, 1, 0) z (0, 0, 1) at (-40, 175, 0)
sketch "Sketch65" plane through (0, 175, 0) normal (0, 1, 0) x (-1, 0, 0)
  circle A0 centre (115, 560) radius 4.75
  circle A1 centre (115, 560) radius 6.25
  circle A2 centre (115, 560) radius 6.25
  constraint concentric A0 A2
extrude "Extrude58" cut sketch "Sketch65" against normal blind 25 bodies 8
move_body "Move26" bodies 9 to x (1, 0, 0) y (0, 1, 0) z (0, 0, 1) at (0, -30, 0)
sketch "Sketch66" plane through (0, 20, 0) normal (0, 1, 0) x (-1, 0, 0)
  arc A0 (75, 255) -> (80, 250) centre (80, 255) ccw
  line L0 (80, 250) -> (115, 250)
  arc A1 (115, 250) -> (120, 255) centre (115, 255) ccw
  line L1 (120, 255) -> (120, 470)
  arc A2 (120, 470) -> (115, 475) centre (115, 470) ccw
  line L2 (115, 475) -> (80, 475)
  arc A3 (80, 475) -> (75, 470) centre (80, 470) ccw
  line L3 (75, 470) -> (75, 255)
  arc A4 (115, 467.5) -> (110, 467.5) centre (112.5, 467.5) ccw
  line L4 (115, 467.5) -> (115, 257.5)
  arc A5 (110, 257.5) -> (115, 257.5) centre (112.5, 257.5) ccw
  line L5 (110, 257.5) -> (110, 467.5)
  circle A6 centre (85, 420) radius 5
  circle A7 centre (85, 305) radius 5
  circle A8 centre (85, 305) radius 5
  circle A9 centre (85, 420) radius 5
  constraint concentric A7 A8
  constraint concentric A6 A9
move_body "Move27" bodies 5 to x (1, 0, 0) y (0, 1, 0) z (0, 0, 1) at (150, 0, 0)
equation "d69 = 'NOW PLAYING'"
